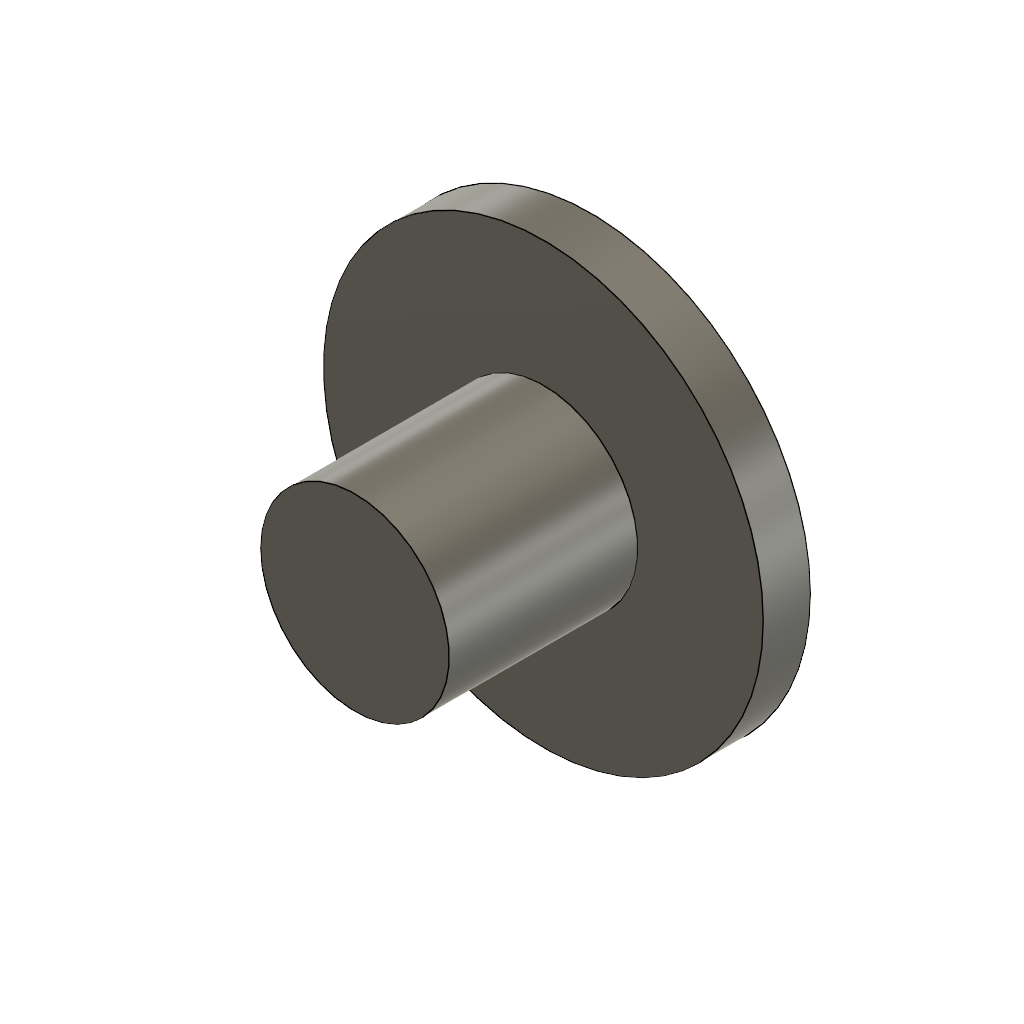
rev_join_flange (Autodesk Fusion 360 design; units mm, degrees)
part number: 2026-11-13-14-41-19-839
Autodesk Fusion 360 part; units mm, degrees
sketch "Sketch1" plane through (0, 0, 0) normal (0, 0, 1) x (1, 0, 0)
  circle A0 centre (0, 0) radius 6
extrude "Extrude1" add sketch "Sketch1" along normal blind 20
sketch "Sketch2" plane through (0, 0, 0) normal (0, 1, 0) x (1, 0, 0)
  line L0 (5, -5) -> (14, -5)
  line L1 (14, -5) -> (14, -8)
  line L2 (14, -8) -> (5, -8)
  line L3 (5, -8) -> (5, -5)
revolve "Revolve1" add sketch "Sketch2" angle 360 about axis through (0, 0, 1.75) along (0, 0, 1)
